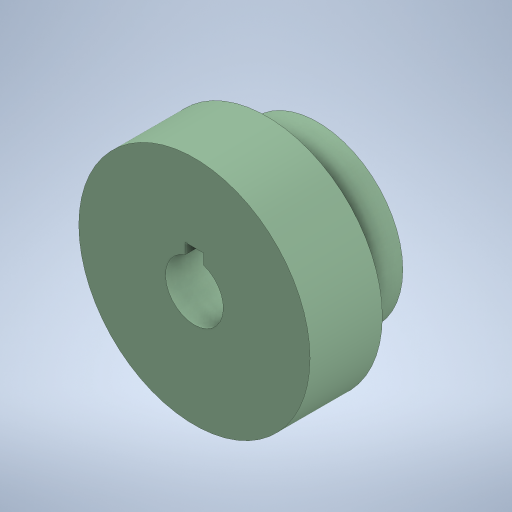
# Autodesk Inventor part: Gear4(output)
Saved by Autodesk Inventor 2023 (Build 270158000, 158)
## iProperties
Created: 2024-05-11
Part Number: Gear4(output)
Material: Generic
Document SubType Name: Modeling
Designer: BenFr
Density: 1 g/cm^3
Appearance: Rubber - Green
Author: BenFr
Autodesk Inventor part; units mm, degrees
ref_plane "YZ Plane" through (0, 0, 0) normal (1, 0, 0) x (0, 1, 0)
ref_plane "XZ Plane" through (0, 0, 0) normal (0, 1, 0) x (-1, 0, 0)
ref_plane "XY Plane" through (0, 0, 0) normal (0, 0, 1) x (1, 0, 0)
sketch "Sketch2" plane through (0, 0, 0) normal (0, 1, 0) x (-1, 0, 0)
  line L0 (0, 0) -> (50.8, 0)
  line L1 (50.8, 0) -> (50.8, -31.75)
  line L2 (0, 0) -> (0, -54.1)
  line L3 (0, -54.1) -> (37.465, -54.1)
  line L4 (37.465, -54.1) -> (37.465, -31.75)
  line L5 (37.465, -31.75) -> (50.8, -31.75)
  line L6 (0, 0) -> (12.7, 0)
  line L7 (12.7, 0) -> (12.7, -54.1)
  dimension "d0" = 50.8
  dimension "d1" = 31.75
  dimension "d2" = 54.1
  dimension "d3" = 37.465
  dimension "d4" = 12.7
  constraints: 16 end point, 4 perpendicular, 2 point on line, 2 vertical, 1 horizontal
  measures "d0" distance of L0.start L0.end
  measures "d1" distance of L0.end L1.end
  measures "d2" distance of L0.start L2.end
  measures "d3" distance of L2.end L3.end
  measures "d4" distance of L0.start L6.end
revolve "Revolution1" add sketch "Sketch2" angle 360 about axis through (0, 0, 0) along (0, 0, -1) contours L0 L1 L5 L4 L3 L7
sketch "Sketch3" plane through (0, 0, 0) normal (0, 0, 1) x (1, 0, 0)
  line L0 (-4, 8.7) -> (4, 8.7)
  line L1 (4, 8.7) -> (4, 16.7)
  line L2 (4, 16.7) -> (-4, 16.7)
  line L3 (-4, 16.7) -> (-4, 8.7)
  circle A0 centre (0, 0) radius 12.7 projected
  line L4 (-4, 8.7) -> (4, 16.7) construction
  line L5 (4, 8.7) -> (-4, 16.7) construction
  point P0 (0, 12.7)
  dimension "d6" = 8
  dimension "d7" = 8
  constraints: 12 end point, 2 midpoint, 2 parallel, 1 horizontal, 1 perpendicular, 1 vertical alignment, 1 other
  measures "d6" distance of L2.end L1.end
  measures "d7" distance of L1.end L0.end
extrude "Extrusion1" cut sketch "Sketch3" against normal through all contours L3 A0 L1 L0 | L3 L2 L1 A0 picked at (0.4513, 10.0092)
body "Solid1"
